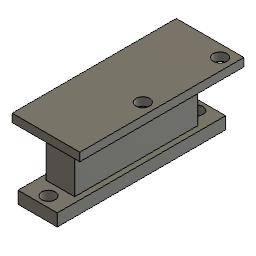
basestation (Autodesk Fusion 360 archive; units mm, degrees)
design "small_lswitch"
part number: 2026-05-09-13-18-58-210
Autodesk Fusion 360 part; units mm, degrees
sketch "Sketch1" plane through (0, 0, 0) normal (0, 1, 0) x (1, 0, 0)
  line L0 (-20, 55) -> (4.75, 55)
  line L1 (4.75, 55) -> (4.75, -5)
  line L2 (4.75, -5) -> (-20, -5)
  line L3 (-20, -5) -> (-20, 55)
  line L4 (-20, 55) -> (-15.875, 55)
  line L5 (-15.875, 45) -> (0.625, 45)
  line L6 (0.625, 45) -> (0.625, 5)
  line L7 (0.625, 5) -> (-15.875, 5)
  line L8 (-15.875, 5) -> (-15.875, 45)
  dimension "d1" = 24.75
  dimension "d2" = 60
  dimension "d3" = 4.125
  dimension "d4" = 10
  dimension "d5" = 16.5
  dimension "d6" = 40
  constraint horizontal L0
  constraint vertical L1
  constraint horizontal L2
  constraint vertical L3
  constraint perpendicular L3 L4
  constraint horizontal L5
  constraint vertical L6
  constraint horizontal L7
  constraint vertical L8
  measures "d1" distance of L0.start L0.end
  measures "d2" distance of L0.start L2.end
  measures "d3" distance of L0.start L4.end
  measures "d4" distance of L4.end L5.start
  measures "d5" distance of L5.start L5.end
  measures "d6" distance of L5.start L7.end
extrude "Extrude1" add sketch "Sketch1" along normal blind 2.31 contours L5 L6 L7 L8 makes body 1
move_body "Move1" bodies 1 to x (1, 0, 0) y (0, 1, 0) z (0, 0, 1) at (0, 16, 0)
extrude "Extrude2" add sketch "Sketch1" along normal blind 3 separate body contours L0 L1 L2 L3 L4 | L5 L6 L7 L8 makes body 2
sketch "Sketch2" plane through (0, 16, 0) normal (0, -1, 0) x (1, 0, 0)
  line L0 (0.625, -5) -> (-15.875, -5)
  line L1 (-15.875, -5) -> (-15.875, -45)
  line L2 (-15.875, -45) -> (0.625, -45)
  line L3 (0.625, -45) -> (0.625, -5)
  line L4 (0.625, -45) -> (0.625, -25)
  line L5 (-2.625, -25) -> (-2.625, -40)
  line L6 (-2.625, -40) -> (-12.625, -40)
  line L7 (-12.625, -40) -> (-12.625, -10)
  line L8 (-12.625, -10) -> (-2.625, -10)
  line L9 (-2.625, -10) -> (-2.625, -40)
  dimension "d11" = 3.25
  dimension "d12" = 10
  dimension "d13" = 30
  constraint coincident L2.end L3.start
  constraint midpoint L3 L4.end
  constraint perpendicular L2 L5
  constraint horizontal L6
  constraint vertical L7
  constraint horizontal L8
  constraint vertical L9
  measures "d11" distance of L4.end L5.start
  measures "d12" distance of L5.end L6.end
  measures "d13" distance of L5.end L8.end
extrude "Extrude3" add sketch "Sketch2" along normal blind 13 contours L5 L6 L7 L8 L9 bodies 1 2
sketch "Sketch3" plane through (0, 3, 0) normal (0, 1, 0) x (-1, 0, 0)
  line L0 (2.625, -40) -> (2.625, -10)
  line L1 (2.625, -10) -> (12.625, -10)
  line L2 (12.625, -10) -> (12.625, -40)
  line L3 (12.625, -40) -> (2.625, -40)
  line L4 (20, -55) -> (20, 5)
  line L5 (20, 5) -> (-4.75, 5)
  line L6 (-4.75, 5) -> (-4.75, -55)
  line L7 (-4.75, -55) -> (20, -55)
  line L8 (-4.75, 5) -> (-4.75, -1)
  circle A0 centre (-1.75, -1) radius 1.65
  circle A1 centre (17, -1) radius 1.65
  line L9 (-4.75, 5) -> (-4.75, -25)
  line L10 (-4.75, -25) -> (20, -25)
  circle A2 centre (-1.75, -49) radius 1.65
  circle A3 centre (17, -49) radius 1.65
  dimension "d16" = 3
  dimension "d17" = 3.3
  dimension "d19" = 3.3
  constraint coincident L5.end L6.start
  constraint coincident L6 L8.end
  constraint midpoint L6 L9.end
  constraint midpoint L4 L10.end
  constraint symmetric A0 L10 A2
  constraint symmetric A1 L10 A3
  measures "d16" distance of L8.end A0.centre
  measures "d17" diameter of A0
  measures "d19" diameter of A1
extrude "Extrude4" cut sketch "Sketch3" against normal blind 100 contours A2 | A3 bodies 1
extrude "Extrude5" cut sketch "Sketch3" against normal blind 100 contours A0 | A1 bodies 1
sketch "Sketch4" plane through (0, 18.31, 0) normal (0, 1, 0) x (-1, 0, 0)
  line L0 (15.875, -5) -> (-0.625, -5)
  line L1 (-0.625, -5) -> (-0.625, -45)
  line L2 (-0.625, -45) -> (15.875, -45)
  line L3 (15.875, -45) -> (15.875, -5)
  line L4 (-0.625, -5) -> (-0.625, -7.93)
  line L5 (15.875, -25) -> (-0.625, -25)
  circle A0 centre (2.2451, -23.2103) radius 1.65
  circle A1 centre (2.275, -42.07) radius 1.65
  dimension "d24" = 2.93
  constraint coincident L0.end L1.start
  constraint perpendicular L0 L4
  constraint midpoint L3 L5.start
  constraint midpoint L1 L5.end
  measures "d24" distance of L0.end L4.end
extrude "Extrude6" cut 1 faces at (-2.625, 11.6667, -20) along direction (-1, 0, 0) blind 1.5 on bodies 1 bodies 1
extrude "Extrude8" cut 1 faces at (-4.125, 11.6667, -20) along direction (-1, 0, 0) blind 3.5 on bodies 1 bodies 1
extrude "Extrude9" add 1 faces at (-7.625, 11.6667, -20) along direction (1, 0, 0) blind 2 on bodies 1 bodies 1
sketch "Sketch5" plane through (0, 18.31, 0) normal (0, 1, 0) x (-1, 0, 0)
  line L0 (15.875, -5) -> (-0.625, -5)
  line L1 (-0.625, -5) -> (-0.625, -45)
  line L2 (-0.625, -45) -> (15.875, -45)
  line L3 (15.875, -45) -> (15.875, -5)
  line L4 (15.875, -5) -> (15.875, -25)
  line L5 (15.875, -25) -> (-0.625, -25)
  constraint coincident L0.start L3.end
  constraint midpoint L3 L4.end
  constraint midpoint L1 L5.end
extrude "Extrude13" cut 1 faces at (-10.375, 18.31, -31.6667) along direction (0, -1, 0) blind 0.3 on bodies 1 bodies 1
sketch "Sketch6" plane through (0, 3, 0) normal (0, 1, 0) x (-1, 0, 0)
  line L0 (5.625, -10) -> (12.625, -10)
  line L1 (12.625, -10) -> (12.625, -40)
  line L2 (12.625, -40) -> (5.625, -40)
  line L3 (5.625, -40) -> (5.625, -10)
  circle A0 centre (17, -1) radius 1.65
  circle A1 centre (-1.75, -1) radius 1.65
  circle A2 centre (17, -49) radius 1.65
  circle A3 centre (-1.75, -49) radius 1.65
  line L4 (20, -55) -> (20, 5)
  line L5 (20, 5) -> (-4.75, 5)
  line L6 (-4.75, 5) -> (-4.75, -55)
  line L7 (-4.75, -55) -> (20, -55)
  line L8 (-4.75, -4.9694) -> (20, -4.9694)
  line L9 (20, -45) -> (-5, -45)
  constraint coincident L6 L8.start
  constraint coincident L4 L8.end
  constraint perpendicular L4 L8
  constraint coincident L4 L9.start
  constraint perpendicular L6 L9
extrude "Extrude14" cut sketch "Sketch6" against normal blind 100 contours L4 L6 L7 L9 | L4 L5 L6 L8 bodies 1
sketch "Sketch7" plane through (0, 3, 0) normal (0, 1, 0) x (-1, 0, 0)
  line L0 (-4.75, -45) -> (20, -45)
  line L1 (20, -45) -> (20, -4.9694)
  line L2 (20, -4.9694) -> (-4.75, -4.9694)
  line L3 (-4.75, -4.9694) -> (-4.75, -45)
  line L4 (5.625, -10) -> (12.625, -10)
  line L5 (12.625, -10) -> (12.625, -40)
  line L6 (12.625, -40) -> (5.625, -40)
  line L7 (5.625, -40) -> (5.625, -10)
  circle A0 centre (-3, -7) radius 1.65
  line L8 (7.625, -4.9694) -> (7.625, -45)
  circle A1 centre (18.25, -7) radius 1.65
  line L9 (-4.75, -24.9847) -> (20, -24.9847)
  circle A2 centre (-3, -42.9694) radius 1.65
  circle A3 centre (18.25, -42.9694) radius 1.65
  dimension "d47" = 3.3
  constraint midpoint L2 L8.start
  constraint midpoint L0 L8.end
  constraint symmetric A0 L8 A1
  constraint midpoint L3 L9.start
  constraint midpoint L1 L9.end
  constraint symmetric A0 L9 A2
  constraint symmetric A1 L9 A3
  measures "d47" diameter of A0
extrude "Extrude15" cut sketch "Sketch7" against normal blind 100 contours A0 | A1 | A2 | A3 bodies 1
extrude "Extrude16" add 1 faces at (-20, 2, -31.6565) along direction (-1, 0, 0) blind 1 on bodies 1 bodies 1
extrude "Extrude17" add 1 faces at (4.75, 1, -31.6565) along direction (1, 0, 0) blind 1 on bodies 1 bodies 1
extrude "Extrude18" add 1 faces at (-12.0833, 2, -4.9694) along direction (0, 0, 1) blind 0.5 on bodies 1 bodies 1
extrude "Extrude19" add 1 faces at (-12.0833, 2, -45) along direction (0, 0, -1) blind 0.5 on bodies 1 bodies 1
sketch "Sketch8" plane through (0, 3, 0) normal (0, 1, 0) x (-1, 0, 0)
  line L0 (5.625, -10) -> (12.625, -10)
  line L1 (12.625, -10) -> (12.625, -40)
  line L2 (12.625, -40) -> (5.625, -40)
  line L3 (5.625, -40) -> (5.625, -10)
  line L4 (21, -45.5) -> (21, -4.4694)
  line L5 (21, -4.4694) -> (-5.75, -4.4694)
  line L6 (-5.75, -4.4694) -> (-5.75, -45.5)
  line L7 (-5.75, -45.5) -> (21, -45.5)
  circle A0 centre (-3, -7) radius 1.65
  circle A1 centre (18.25, -7) radius 1.65
  circle A2 centre (-3, -42.9694) radius 1.65
  circle A3 centre (18.25, -42.9694) radius 1.65
  circle A4 centre (9, -7) radius 1.65
  circle A5 centre (9, -43) radius 1.65
  line L8 (2.7242, -4.4694) -> (2.7242, -45.5)
  line L9 (5, -45.5) -> (5, -4.4694)
  line L10 (13.9274, -4.4694) -> (13.9274, -45.5)
  dimension "d60" = 3.3
  dimension "d61" = 3.3
  constraint coincident L5 L8.start
  constraint coincident L7 L8.end
  constraint perpendicular L7 L8
  constraint coincident L7 L9.start
  constraint coincident L5 L9.end
  constraint perpendicular L5 L9
  constraint coincident L5 L10.start
  constraint coincident L7 L10.end
  constraint perpendicular L7 L10
  measures "d60" diameter of A4
  measures "d61" diameter of A5
extrude "Extrude21" cut sketch "Sketch8" against normal blind 18 contours L4 L5 L7 L10 | L5 L7 L8 L9 | L5 L6 L7 L8 bodies 1
extrude "Extrude22" cut sketch "Sketch8" against normal blind 15 contours A4 | A5 bodies 1
extrude "Extrude23" add 1 faces at (-5, 1, -18.1463) along direction (1, 0, 0) blind 0.675 on bodies 1 bodies 1
extrude "Extrude24" cut sketch "Sketch4" against normal blind 8 contours A0 | A1 bodies 1
equation "d1 = 16.5 mm + 8.25 mm"
equation "d3 = ( 8.25 / 2 ) * 1 mm"
equation "d5 = 20.625 mm - 4.125 mm"
equation "d24 = 1.28 mm + 1.65 mm"

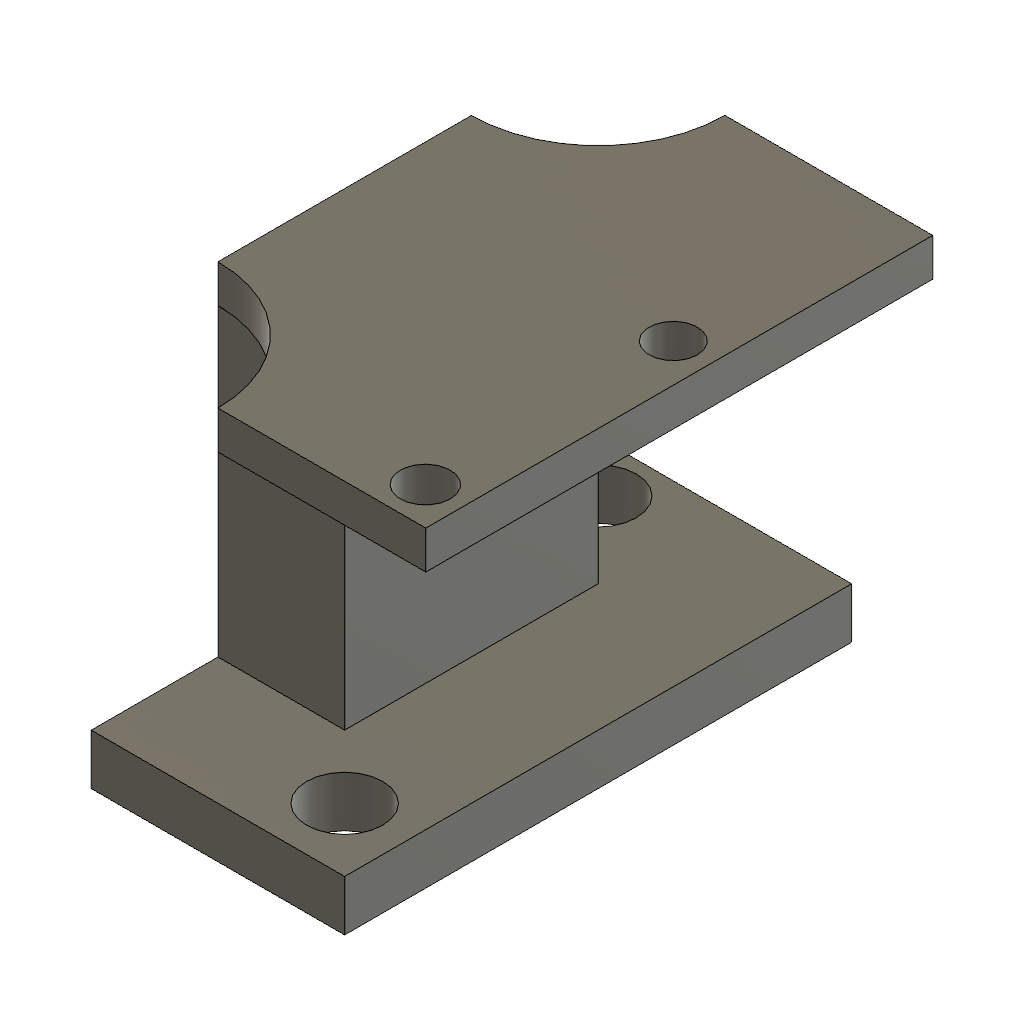
design "lswitch_mount"
part number: 2026-05-09-11-11-11-212
Autodesk Fusion 360 part; units mm, degrees
sketch "Sketch1" plane through (0, 0, 0) normal (0, 1, 0) x (1, 0, 0)
  line L0 (-20, 10) -> (0, 10)
  line L1 (0, 10) -> (0, -10)
  line L2 (0, -10) -> (-20, -10)
  line L3 (-20, -10) -> (-20, 10)
  line L4 (0, 0) -> (0, 10)
  line L5 (-15, 0) -> (-15, 5)
  line L6 (-15, 5) -> (-5, 5)
  line L7 (-5, 5) -> (-5, -5)
  line L8 (-5, -5) -> (-15, -5)
  line L9 (-15, -5) -> (-15, 5)
  circle A0 centre (-17.5, 7.5) radius 1.5
  circle A1 centre (-2.5, 7.5) radius 1.5
  circle A2 centre (-2.5, -7.5) radius 1.5
  circle A3 centre (-17.5, -7.5) radius 1.5
  dimension "d1" = 20
  dimension "d2" = 20
  dimension "d4" = 5
  dimension "d5" = 10
  dimension "d6" = 10
  dimension "d7" = 3
  dimension "d8" = 3
  dimension "d9" = 3
  dimension "d10" = 3
  constraint horizontal L0
  constraint vertical L1
  constraint horizontal L2
  constraint vertical L3
  constraint coincident L4.start origin
  constraint perpendicular L0 L4
  constraint horizontal L6
  constraint vertical L7
  constraint horizontal L8
  constraint vertical L9
  measures "d1" distance of L0.start L0.end
  measures "d2" distance of L0.start L2.end
  measures "d4" distance of L5.start L5.end
  measures "d5" distance of L5.end L6.end
  measures "d6" distance of L5.end L8.end
  measures "d7" diameter of A0
  measures "d8" diameter of A1 L4
  measures "d9" diameter of A2 L4
  measures "d10" diameter of A3
extrude "Extrude1" add sketch "Sketch1" along normal blind 2
extrude "Extrude2" add sketch "Sketch1" along normal blind 15.5 contours L5 L6 L7 L8 L9
sketch "Sketch2" plane through (-5, 0, 0) normal (1, 0, 0) x (0, 0, -1)
  line L0 (-5, 2) -> (5, 2)
  line L1 (5, 2) -> (5, 15.5)
  line L2 (5, 15.5) -> (-5, 15.5)
  line L3 (-5, 15.5) -> (-5, 2)
  line L4 (5, 15.5) -> (5, 14)
  line L5 (5, 14) -> (-5, 14)
  line L6 (-5, 14) -> (-5, 15.5)
  line L7 (-5, 14) -> (-4, 14)
  line L8 (-4, 14) -> (-4, 12)
  line L9 (-4, 12) -> (-5, 12)
  line L10 (-5, 12) -> (-5, 14)
  line L11 (4, 14) -> (5, 14)
  line L12 (5, 14) -> (5, 12)
  line L13 (5, 12) -> (4, 12)
  line L14 (4, 12) -> (4, 14)
  constraint vertical L4
  constraint horizontal L5
  constraint vertical L6
  constraint coincident L1 L4.end
  constraint coincident L2.end L3.start
  constraint horizontal L7
  constraint vertical L8
  constraint horizontal L9
  constraint vertical L10
  constraint horizontal L11
  constraint vertical L12
  constraint horizontal L13
  constraint vertical L14
  constraint coincident L1 L12.end
  constraint coincident L5 L11.start
extrude "Extrude3" add sketch "Sketch2" along normal blind 8.2 contours L1 L2 L3 L4 L5 L6 L7 L11
sketch "Sketch3" plane through (0, 0, 5) normal (0, 0, 1) x (1, 0, 0)
  line L0 (-15, 2) -> (-5, 2)
  line L1 (-5, 2) -> (-5, 14)
  line L2 (-5, 14) -> (3.2, 14)
  line L3 (3.2, 14) -> (3.2, 15.5)
  line L4 (3.2, 15.5) -> (-15, 15.5)
  line L5 (-15, 15.5) -> (-15, 2)
  line L6 (-5, 15.5) -> (-5, 14)
  line L7 (-5, 15.5) -> (-5, 14)
  constraint coincident L4 L6.start
  constraint coincident L1.end L2.start
  constraint perpendicular L2 L6
extrude "Extrude4" add sketch "Sketch3" along normal blind 5 contours L2 L3 L4 L6 L7
sketch "Sketch4" plane through (0, 0, -5) normal (0, 0, -1) x (-1, 0, 0)
  line L0 (5, 2) -> (15, 2)
  line L1 (15, 2) -> (15, 15.5)
  line L2 (15, 15.5) -> (-3.2, 15.5)
  line L3 (-3.2, 15.5) -> (-3.2, 14)
  line L4 (-3.2, 14) -> (5, 14)
  line L5 (5, 14) -> (5, 2)
  line L6 (5, 14) -> (5, 15.5)
  constraint coincident L4.end L5.start
  constraint coincident L2 L6.end
  constraint perpendicular L2 L6
extrude "Extrude5" add sketch "Sketch4" along normal blind 5 contours L2 L3 L4 L6
fillet "Fillet1" radius 5 1 edges at (-5, 14.75, 5)
fillet "Fillet2" radius 5 1 edges at (-5, 14.75, -5)
sketch "Sketch5" plane through (0, 15.5, 0) normal (0, 1, 0) x (-1, 0, 0)
  line L0 (15, 5) -> (10, 5)
  arc A0 (5, 10) -> (10, 5) centre (10, 10) ccw
  line L1 (5, 10) -> (-3.2, 10)
  line L2 (-3.2, 10) -> (-3.2, -10)
  line L3 (-3.2, -10) -> (5, -10)
  arc A1 (10, -5) -> (5, -10) centre (10, -10) ccw
  line L4 (10, -5) -> (15, -5)
  line L5 (15, -5) -> (15, 5)
  line L6 (15, 5) -> (15, 0)
  line L7 (15, 0) -> (-3.2, 0)
  circle A2 centre (-1.6896, -1.2726) radius 0.95
  circle A3 centre (-1.7043, 8.5216) radius 0.986
  constraint coincident L0.start L5.end
  constraint midpoint L5 L6.end
  constraint midpoint L2 L7.end
extrude "Extrude8" add sketch "Sketch2" along normal blind 3 contours L3 L5 L7 L8 L9 L10 | L1 L5 L11 L12 L13 L14
sketch "Sketch6" plane through (0, 0, -5) normal (0, 0, -1) x (-1, 0, 0)
  line L0 (10, 15.5) -> (10, 14)
  line L1 (10, 14) -> (2, 14)
  line L2 (2, 14) -> (2, 12)
  line L3 (2, 12) -> (5, 12)
  line L4 (5, 12) -> (5, 2)
  line L5 (5, 2) -> (15, 2)
  line L6 (15, 2) -> (15, 15.5)
  line L7 (15, 15.5) -> (10, 15.5)
  line L8 (5, 12) -> (2, 14)
  constraint coincident L3.end L4.start
  constraint coincident L1.end L2.start
extrude "Extrude9" cut sketch "Sketch6" against normal blind 100 contours L2 L3 L8
sketch "Sketch7" plane through (0, 15.5, 0) normal (0, 1, 0) x (-1, 0, 0)
sketch "Sketch8" plane through (0, 15.5, 0) normal (0, 1, 0) x (-1, 0, 0)
  line L0 (15, 5) -> (10, 5)
  arc A0 (5, 10) -> (10, 5) centre (10, 10) ccw
  line L1 (5, 10) -> (-3.2, 10)
  line L2 (-3.2, 10) -> (-3.2, -10)
  line L3 (-3.2, -10) -> (5, -10)
  arc A1 (10, -5) -> (5, -10) centre (10, -10) ccw
  line L4 (10, -5) -> (15, -5)
  line L5 (15, -5) -> (15, 5)
  line L6 (15, 5) -> (15, 0)
  line L7 (15, 0) -> (-3.2, 0)
  dimension "d38" = 5
  constraint coincident L0.start L5.end
  constraint perpendicular L0 L6
  constraint midpoint L2 L7.end
  measures "d38" distance of L0.start L6.end
sketch "Sketch9" plane through (0, 15.5, 0) normal (0, 1, 0) x (-1, 0, 0)
  line L0 (15, 5) -> (10, 5)
  arc A0 (5, 10) -> (10, 5) centre (10, 10) ccw
  line L1 (5, 10) -> (-3.2, 10)
  line L2 (-3.2, 10) -> (-3.2, -10)
  line L3 (-3.2, -10) -> (5, -10)
  arc A1 (10, -5) -> (5, -10) centre (10, -10) ccw
  line L4 (10, -5) -> (15, -5)
  line L5 (15, -5) -> (15, 5)
  line L6 (12, -5) -> (12, 5)
  constraint coincident L4 L6.start
  constraint coincident L0 L6.end
  constraint perpendicular L0 L6
extrude "Extrude11" cut sketch "Sketch9" against normal blind 28 contours L0 L4 L5 L6
sketch "Sketch10" plane through (0, 2, 0) normal (0, 1, 0) x (-1, 0, 0)
  circle A0 centre (17.5, 7.5) radius 1.5
  circle A1 centre (17.5, -7.5) radius 1.5
  circle A2 centre (2.5, -7.5) radius 1.5
  circle A3 centre (2.5, 7.5) radius 1.5
  line L0 (5, 5) -> (12, 5)
  line L1 (12, 5) -> (15, 5)
  line L2 (15, 5) -> (15, -5)
  line L3 (15, -5) -> (12, -5)
  line L4 (12, -5) -> (5, -5)
  line L5 (5, -5) -> (5, 5)
  line L6 (0, 10) -> (0, -10)
  line L7 (0, -10) -> (20, -10)
  line L8 (20, -10) -> (20, 10)
  line L9 (20, 10) -> (0, 10)
  line L10 (12, 5) -> (12, 10)
  line L11 (12, -5) -> (12, -10)
  constraint coincident L0.end L1.start
  constraint coincident L9 L10.end
  constraint perpendicular L9 L10
  constraint coincident L3.end L4.start
  constraint perpendicular L3 L11
extrude "Extrude12" cut sketch "Sketch10" against normal blind 8 contours L1 L2 L3 L7 L8 L9 L10 L11
extrude "Extrude13" cut 1 faces at (-12, 11, -1.6667) along direction (1, 0, 0) blind 2
delete_face "DeleteFace1" 1 faces at (-1.0019, 1.3333, -7.4252)
sketch "Sketch11" plane through (0, 2, 0) normal (0, 1, 0) x (-1, 0, 0)
  line L0 (10, 5) -> (10, 10)
  line L1 (10, 10) -> (0, 10)
  line L2 (0, 10) -> (0, -10)
  line L3 (0, -10) -> (10, -10)
  line L4 (10, -10) -> (10, -5)
  line L5 (10, -5) -> (5, -5)
  line L6 (5, -5) -> (5, 5)
  line L7 (5, 5) -> (10, 5)
  circle A0 centre (2.5, 7.5) radius 1.5
  circle A1 centre (8, -8) radius 1.5
  dimension "d47" = 3
  measures "d47" diameter of A1
extrude "Extrude14" cut sketch "Sketch11" against normal blind 11 contours A1
extrude "Extrude15" cut sketch "Sketch5" against normal blind 4 contours A2 | A3
scale "Scale1" factor 2 about (3.2, 14, -10) bodies 1
